Autodesk Fusion 360 part; units mm, degrees
(part 3 of 3)
sketch "Sketch252" plane through (-23.6, 0, 0) normal (1, 0, 0) x (0, 0, -1)
  line L0 (-13.8, -29.146) -> (13.8, -29.146)
  line L1 (13.8, -29.146) -> (13.8, -25.6)
  line L2 (13.8, -25.6) -> (-13.8, -25.6)
  line L3 (-13.8, -25.6) -> (-13.8, -29.146)
loft "Loft72" add profiles "Sketch251", "Sketch252" section 1 section 2 separate body makes body 180
ref_plane "WorkPlane253" through (-24.4, 0, 0) normal (1, 0, 0) x (0, 1, 0)
sketch "Sketch253" plane through (-24.4, 0, 0) normal (1, 0, 0) x (0, 0, -1)
  line L0 (-13.45, -28.8108) -> (13.45, -28.8108)
  line L1 (13.45, -28.8108) -> (13.45, -25.4)
  line L2 (13.45, -25.4) -> (-13.45, -25.4)
  line L3 (-13.45, -25.4) -> (-13.45, -28.8108)
ref_plane "WorkPlane254" through (-21.6, 0, 0) normal (1, 0, 0) x (0, 1, 0)
sketch "Sketch254" plane through (-21.6, 0, 0) normal (1, 0, 0) x (0, 0, -1)
  line L0 (-14.6091, -29.8371) -> (14.6091, -29.8371)
  line L1 (14.6091, -29.8371) -> (14.6091, -26)
  line L2 (14.6091, -26) -> (-14.6091, -26)
  line L3 (-14.6091, -26) -> (-14.6091, -29.8371)
loft "Loft73" add profiles "Sketch253", "Sketch254" section 1 section 2 separate body makes body 181
ref_plane "WorkPlane255" through (-22.4, 0, 0) normal (1, 0, 0) x (0, 1, 0)
sketch "Sketch255" plane through (-22.4, 0, 0) normal (1, 0, 0) x (0, 0, -1)
  line L0 (-14.325, -29.6278) -> (14.325, -29.6278)
  line L1 (14.325, -29.6278) -> (14.325, -25.9)
  line L2 (14.325, -25.9) -> (-14.325, -25.9)
  line L3 (-14.325, -25.9) -> (-14.325, -29.6278)
ref_plane "WorkPlane256" through (-17.6, 0, 0) normal (1, 0, 0) x (0, 1, 0)
sketch "Sketch256" plane through (-17.6, 0, 0) normal (1, 0, 0) x (0, 0, -1)
  line L0 (-15.7, -30.2773) -> (15.7, -30.2773)
  line L1 (15.7, -30.2773) -> (15.7, -26)
  line L2 (15.7, -26) -> (-15.7, -26)
  line L3 (-15.7, -26) -> (-15.7, -30.2773)
loft "Loft74" add profiles "Sketch255", "Sketch256" section 1 section 2 separate body makes body 182
ref_plane "WorkPlane257" through (-18.4, 0, 0) normal (1, 0, 0) x (0, 1, 0)
sketch "Sketch257" plane through (-18.4, 0, 0) normal (1, 0, 0) x (0, 0, -1)
  line L0 (-15.4818, -30.2013) -> (15.4818, -30.2013)
  line L1 (15.4818, -30.2013) -> (15.4818, -26)
  line L2 (15.4818, -26) -> (-15.4818, -26)
  line L3 (-15.4818, -26) -> (-15.4818, -30.2013)
ref_plane "WorkPlane258" through (-11.6, 0, 0) normal (1, 0, 0) x (0, 1, 0)
sketch "Sketch258" plane through (-11.6, 0, 0) normal (1, 0, 0) x (0, 0, -1)
  line L0 (-17.3364, -30.7044) -> (17.3364, -30.7044)
  line L1 (17.3364, -30.7044) -> (17.3364, -26)
  line L2 (17.3364, -26) -> (-17.3364, -26)
  line L3 (-17.3364, -26) -> (-17.3364, -30.7044)
loft "Loft75" add profiles "Sketch257", "Sketch258" section 1 section 2 separate body makes body 183
ref_plane "WorkPlane259" through (-12.4, 0, 0) normal (1, 0, 0) x (0, 1, 0)
sketch "Sketch259" plane through (-12.4, 0, 0) normal (1, 0, 0) x (0, 0, -1)
  line L0 (-17.1182, -30.6602) -> (17.1182, -30.6602)
  line L1 (17.1182, -30.6602) -> (17.1182, -26)
  line L2 (17.1182, -26) -> (-17.1182, -26)
  line L3 (-17.1182, -26) -> (-17.1182, -30.6602)
ref_plane "WorkPlane260" through (-5.6, 0, 0) normal (1, 0, 0) x (0, 1, 0)
sketch "Sketch260" plane through (-5.6, 0, 0) normal (1, 0, 0) x (0, 0, -1)
  line L0 (-18.9727, -30.9332) -> (18.9727, -30.9332)
  line L1 (18.9727, -30.9332) -> (18.9727, -26)
  line L2 (18.9727, -26) -> (-18.9727, -26)
  line L3 (-18.9727, -26) -> (-18.9727, -30.9332)
loft "Loft76" add profiles "Sketch259", "Sketch260" section 1 section 2 separate body makes body 184
ref_plane "WorkPlane261" through (-6.4, 0, 0) normal (1, 0, 0) x (0, 1, 0)
sketch "Sketch261" plane through (-6.4, 0, 0) normal (1, 0, 0) x (0, 0, -1)
  line L0 (-18.7545, -30.9125) -> (18.7545, -30.9125)
  line L1 (18.7545, -30.9125) -> (18.7545, -26)
  line L2 (18.7545, -26) -> (-18.7545, -26)
  line L3 (-18.7545, -26) -> (-18.7545, -30.9125)
ref_plane "WorkPlane262" through (0.4, 0, 0) normal (1, 0, 0) x (0, 1, 0)
sketch "Sketch262" plane through (0.4, 0, 0) normal (1, 0, 0) x (0, 0, -1)
  line L0 (-20.5, -31) -> (20.5, -31)
  line L1 (20.5, -31) -> (20.5, -26)
  line L2 (20.5, -26) -> (-20.5, -26)
  line L3 (-20.5, -26) -> (-20.5, -31)
loft "Loft77" add profiles "Sketch261", "Sketch262" section 1 section 2 separate body makes body 185
ref_plane "WorkPlane263" through (-0.4, 0, 0) normal (1, 0, 0) x (0, 1, 0)
sketch "Sketch263" plane through (-0.4, 0, 0) normal (1, 0, 0) x (0, 0, -1)
  line L0 (-20.3909, -30.9997) -> (20.3909, -30.9997)
  line L1 (20.3909, -30.9997) -> (20.3909, -26)
  line L2 (20.3909, -26) -> (-20.3909, -26)
  line L3 (-20.3909, -26) -> (-20.3909, -30.9997)
ref_plane "WorkPlane264" through (30.4, 0, 0) normal (1, 0, 0) x (0, 1, 0)
sketch "Sketch264" plane through (30.4, 0, 0) normal (1, 0, 0) x (0, 0, -1)
  line L0 (-20.5, -31) -> (20.5, -31)
  line L1 (20.5, -31) -> (20.5, -26)
  line L2 (20.5, -26) -> (-20.5, -26)
  line L3 (-20.5, -26) -> (-20.5, -31)
loft "Loft78" add profiles "Sketch263", "Sketch264" section 1 section 2 separate body makes body 186
ref_plane "WorkPlane265" through (29.6, 0, 0) normal (1, 0, 0) x (0, 1, 0)
sketch "Sketch265" plane through (29.6, 0, 0) normal (1, 0, 0) x (0, 0, -1)
  line L0 (-20.5, -31) -> (20.5, -31)
  line L1 (20.5, -31) -> (20.5, -26)
  line L2 (20.5, -26) -> (-20.5, -26)
  line L3 (-20.5, -26) -> (-20.5, -31)
ref_plane "WorkPlane266" through (60.4, 0, 0) normal (1, 0, 0) x (0, 1, 0)
sketch "Sketch266" plane through (60.4, 0, 0) normal (1, 0, 0) x (0, 0, -1)
  line L0 (-20.5, -31) -> (20.5, -31)
  line L1 (20.5, -31) -> (20.5, -26)
  line L2 (20.5, -26) -> (-20.5, -26)
  line L3 (-20.5, -26) -> (-20.5, -31)
loft "Loft79" add profiles "Sketch265", "Sketch266" section 1 section 2 separate body makes body 187
ref_plane "WorkPlane267" through (59.6, 0, 0) normal (1, 0, 0) x (0, 1, 0)
sketch "Sketch267" plane through (59.6, 0, 0) normal (1, 0, 0) x (0, 0, -1)
  line L0 (-20.5, -31) -> (20.5, -31)
  line L1 (20.5, -31) -> (20.5, -26)
  line L2 (20.5, -26) -> (-20.5, -26)
  line L3 (-20.5, -26) -> (-20.5, -31)
ref_plane "WorkPlane268" through (90.4, 0, 0) normal (1, 0, 0) x (0, 1, 0)
sketch "Sketch268" plane through (90.4, 0, 0) normal (1, 0, 0) x (0, 0, -1)
  line L0 (-20.5, -31) -> (20.5, -31)
  line L1 (20.5, -31) -> (20.5, -26)
  line L2 (20.5, -26) -> (-20.5, -26)
  line L3 (-20.5, -26) -> (-20.5, -31)
loft "Loft80" add profiles "Sketch267", "Sketch268" section 1 section 2 separate body makes body 188
ref_plane "WorkPlane269" through (89.6, 0, 0) normal (1, 0, 0) x (0, 1, 0)
sketch "Sketch269" plane through (89.6, 0, 0) normal (1, 0, 0) x (0, 0, -1)
  line L0 (-20.5, -31) -> (20.5, -31)
  line L1 (20.5, -31) -> (20.5, -26)
  line L2 (20.5, -26) -> (-20.5, -26)
  line L3 (-20.5, -26) -> (-20.5, -31)
ref_plane "WorkPlane270" through (120.4, 0, 0) normal (1, 0, 0) x (0, 1, 0)
sketch "Sketch270" plane through (120.4, 0, 0) normal (1, 0, 0) x (0, 0, -1)
  line L0 (-20.5, -30.9848) -> (20.5, -30.9848)
  line L1 (20.5, -30.9848) -> (20.5, -26)
  line L2 (20.5, -26) -> (-20.5, -26)
  line L3 (-20.5, -26) -> (-20.5, -30.9848)
loft "Loft81" add profiles "Sketch269", "Sketch270" section 1 section 2 separate body makes body 189
ref_plane "WorkPlane271" through (119.6, 0, 0) normal (1, 0, 0) x (0, 1, 0)
sketch "Sketch271" plane through (119.6, 0, 0) normal (1, 0, 0) x (0, 0, -1)
  line L0 (-20.5, -31) -> (20.5, -31)
  line L1 (20.5, -31) -> (20.5, -26)
  line L2 (20.5, -26) -> (-20.5, -26)
  line L3 (-20.5, -26) -> (-20.5, -31)
ref_plane "WorkPlane272" through (122.4, 0, 0) normal (1, 0, 0) x (0, 1, 0)
sketch "Sketch272" plane through (122.4, 0, 0) normal (1, 0, 0) x (0, 0, -1)
  line L0 (-20.4147, -30.8142) -> (20.4147, -30.8142)
  line L1 (20.4147, -30.8142) -> (20.4147, -25.9059)
  line L2 (20.4147, -25.9059) -> (-20.4147, -25.9059)
  line L3 (-20.4147, -25.9059) -> (-20.4147, -30.8142)
loft "Loft82" add profiles "Sketch271", "Sketch272" section 1 section 2 separate body makes body 190
ref_plane "WorkPlane273" through (121.6, 0, 0) normal (1, 0, 0) x (0, 1, 0)
sketch "Sketch273" plane through (121.6, 0, 0) normal (1, 0, 0) x (0, 0, -1)
  line L0 (-20.5, -30.939) -> (20.5, -30.939)
  line L1 (20.5, -30.939) -> (20.5, -26)
  line L2 (20.5, -26) -> (-20.5, -26)
  line L3 (-20.5, -26) -> (-20.5, -30.939)
ref_plane "WorkPlane274" through (132.0667, 0, 0) normal (1, 0, 0) x (0, 1, 0)
sketch "Sketch274" plane through (132.0667, 0, 0) normal (1, 0, 0) x (0, 0, -1)
  line L0 (-18.3534, -28.16) -> (18.3534, -28.16)
  line L1 (18.3534, -28.16) -> (18.3534, -23.6314)
  line L2 (18.3534, -23.6314) -> (-18.3534, -23.6314)
  line L3 (-18.3534, -23.6314) -> (-18.3534, -28.16)
loft "Loft83" add profiles "Sketch273", "Sketch274" section 1 section 2 separate body makes body 191
ref_plane "WorkPlane275" through (131.2667, 0, 0) normal (1, 0, 0) x (0, 1, 0)
sketch "Sketch275" plane through (131.2667, 0, 0) normal (1, 0, 0) x (0, 0, -1)
  line L0 (-18.524, -28.3803) -> (18.524, -28.3803)
  line L1 (18.524, -28.3803) -> (18.524, -23.8196)
  line L2 (18.524, -23.8196) -> (-18.524, -23.8196)
  line L3 (-18.524, -23.8196) -> (-18.524, -28.3803)
ref_plane "WorkPlane276" through (143.7333, 0, 0) normal (1, 0, 0) x (0, 1, 0)
sketch "Sketch276" plane through (143.7333, 0, 0) normal (1, 0, 0) x (0, 0, -1)
  line L0 (-15.8657, -24.9301) -> (15.8657, -24.9301)
  line L1 (15.8657, -24.9301) -> (15.8657, -20.8863)
  line L2 (15.8657, -20.8863) -> (-15.8657, -20.8863)
  line L3 (-15.8657, -20.8863) -> (-15.8657, -24.9301)
loft "Loft84" add profiles "Sketch275", "Sketch276" section 1 section 2 separate body makes body 192
ref_plane "WorkPlane277" through (142.9333, 0, 0) normal (1, 0, 0) x (0, 1, 0)
sketch "Sketch277" plane through (142.9333, 0, 0) normal (1, 0, 0) x (0, 0, -1)
  line L0 (-16.0363, -25.1527) -> (16.0363, -25.1527)
  line L1 (16.0363, -25.1527) -> (16.0363, -21.0745)
  line L2 (16.0363, -21.0745) -> (-16.0363, -21.0745)
  line L3 (-16.0363, -21.0745) -> (-16.0363, -25.1527)
ref_plane "WorkPlane278" through (155.4, 0, 0) normal (1, 0, 0) x (0, 1, 0)
sketch "Sketch278" plane through (155.4, 0, 0) normal (1, 0, 0) x (0, 0, -1)
  line L0 (-13.3779, -21.6616) -> (13.3779, -21.6616)
  line L1 (13.3779, -21.6616) -> (13.3779, -18.1412)
  line L2 (13.3779, -18.1412) -> (-13.3779, -18.1412)
  line L3 (-13.3779, -18.1412) -> (-13.3779, -21.6616)
loft "Loft85" add profiles "Sketch277", "Sketch278" section 1 section 2 separate body makes body 193
ref_plane "WorkPlane279" through (154.6, 0, 0) normal (1, 0, 0) x (0, 1, 0)
sketch "Sketch279" plane through (154.6, 0, 0) normal (1, 0, 0) x (0, 0, -1)
  line L0 (-13.5485, -21.8873) -> (13.5485, -21.8873)
  line L1 (13.5485, -21.8873) -> (13.5485, -18.3294)
  line L2 (13.5485, -18.3294) -> (-13.5485, -18.3294)
  line L3 (-13.5485, -18.3294) -> (-13.5485, -21.8873)
ref_plane "WorkPlane280" through (167.0667, 0, 0) normal (1, 0, 0) x (0, 1, 0)
sketch "Sketch280" plane through (167.0667, 0, 0) normal (1, 0, 0) x (0, 0, -1)
  line L0 (-10.8902, -18.336) -> (10.8902, -18.336)
  line L1 (10.8902, -18.336) -> (10.8902, -15.3961)
  line L2 (10.8902, -15.3961) -> (-10.8902, -15.3961)
  line L3 (-10.8902, -15.3961) -> (-10.8902, -18.336)
loft "Loft86" add profiles "Sketch279", "Sketch280" section 1 section 2 separate body makes body 194
ref_plane "WorkPlane281" through (166.2667, 0, 0) normal (1, 0, 0) x (0, 1, 0)
sketch "Sketch281" plane through (166.2667, 0, 0) normal (1, 0, 0) x (0, 0, -1)
  line L0 (-11.0608, -18.5666) -> (11.0608, -18.5666)
  line L1 (11.0608, -18.5666) -> (11.0608, -15.5843)
  line L2 (11.0608, -15.5843) -> (-11.0608, -15.5843)
  line L3 (-11.0608, -15.5843) -> (-11.0608, -18.5666)
ref_plane "WorkPlane282" through (178.7333, 0, 0) normal (1, 0, 0) x (0, 1, 0)
sketch "Sketch282" plane through (178.7333, 0, 0) normal (1, 0, 0) x (0, 0, -1)
  line L0 (-8.4025, -14.9089) -> (8.4025, -14.9089)
  line L1 (8.4025, -14.9089) -> (8.4025, -12.651)
  line L2 (8.4025, -12.651) -> (-8.4025, -12.651)
  line L3 (-8.4025, -12.651) -> (-8.4025, -14.9089)
loft "Loft87" add profiles "Sketch281", "Sketch282" section 1 section 2 separate body makes body 195
ref_plane "WorkPlane283" through (177.9333, 0, 0) normal (1, 0, 0) x (0, 1, 0)
sketch "Sketch283" plane through (177.9333, 0, 0) normal (1, 0, 0) x (0, 0, -1)
  line L0 (-8.573, -15.1492) -> (8.573, -15.1492)
  line L1 (8.573, -15.1492) -> (8.573, -12.8392)
  line L2 (8.573, -12.8392) -> (-8.573, -12.8392)
  line L3 (-8.573, -12.8392) -> (-8.573, -15.1492)
ref_plane "WorkPlane284" through (190, 0, 0) normal (1, 0, 0) x (0, 1, 0)
sketch "Sketch284" plane through (190, 0, 0) normal (1, 0, 0) x (0, 0, -1)
  line L0 (-6, -11.2) -> (6, -11.2)
  line L1 (6, -11.2) -> (6, -10)
  line L2 (6, -10) -> (-6, -10)
  line L3 (-6, -10) -> (-6, -11.2)
loft "Loft88" add profiles "Sketch283", "Sketch284" section 1 section 2 separate body makes body 196
ref_plane "WorkPlane285" through (-28, 0, 0) normal (1, 0, 0) x (0, 1, 0)
sketch "fair_nose_bulkhead" plane through (-28, 0, 0) normal (1, 0, 0) x (0, 0, -1)
  line L0 (-11.875, -24.5) -> (11.875, -24.5)
  line L1 (11.875, -24.5) -> (11.875, 24.5)
  line L2 (11.875, 24.5) -> (-11.875, 24.5)
  line L3 (-11.875, 24.5) -> (-11.875, -24.5)
  line L4 (-10.5, -23.5) -> (10.5, -23.5)
  line L5 (10.5, -23.5) -> (10.5, 23.5)
  line L6 (10.5, 23.5) -> (-10.5, 23.5)
  line L7 (-10.5, 23.5) -> (-10.5, -23.5)
extrude "Extrude109" add sketch "fair_nose_bulkhead" along normal mid plane 2 separate body makes body 197
ref_plane "WorkPlane286" through (189, 0, 0) normal (1, 0, 0) x (0, 1, 0)
sketch "fair_tail_bulkhead" plane through (189, 0, 0) normal (1, 0, 0) x (0, 0, -1)
  line L0 (-6.2132, -10.2353) -> (6.2132, -10.2353)
  line L1 (6.2132, -10.2353) -> (6.2132, 10.2353)
  line L2 (6.2132, 10.2353) -> (-6.2132, 10.2353)
  line L3 (-6.2132, 10.2353) -> (-6.2132, -10.2353)
extrude "Extrude110" add sketch "fair_tail_bulkhead" along normal mid plane 2 separate body makes body 198
named bodies: "plate_a", "plate_b", "rail_left", "rail_right", "bm_top_s00", "bm_top_s01", "bm_top_s02", "bm_top_s03", "bm_top_s04", "bm_bottom_s00", "bm_bottom_s01", "bm_bottom_s02", "bm_bottom_s03", "bm_bottom_s04", "bm_left_s00", "bm_left_s01", "bm_left_s02", "bm_left_s03", "bm_left_s04", "bm_right_s00", "bm_right_s01", "bm_right_s02", "bm_right_s03", "bm_right_s04", "front_flange", "rear_cap", "graphite_left", "graphite_right", "magnet_N_st0_a0_d0", "magnet_N_st0_a0_d1", "magnet_S_st0_a0_d0", "magnet_S_st0_a0_d1", "magnet_N_st0_a1_d0", "magnet_N_st0_a1_d1", "magnet_S_st0_a1_d0", "magnet_S_st0_a1_d1", "magnet_N_st0_a2_d0", "magnet_N_st0_a2_d1", "magnet_S_st0_a2_d0", "magnet_S_st0_a2_d1", "magnet_N_st0_a3_d0", "magnet_N_st0_a3_d1", "magnet_S_st0_a3_d0", "magnet_S_st0_a3_d1", "magnet_N_st1_a0_d0", "magnet_N_st1_a0_d1", "magnet_S_st1_a0_d0", "magnet_S_st1_a0_d1", "magnet_N_st1_a1_d0", "magnet_N_st1_a1_d1", "magnet_S_st1_a1_d0", "magnet_S_st1_a1_d1", "magnet_N_st1_a2_d0", "magnet_N_st1_a2_d1", "magnet_S_st1_a2_d0", "magnet_S_st1_a2_d1", "magnet_N_st1_a3_d0", "magnet_N_st1_a3_d1", "magnet_S_st1_a3_d0", "magnet_S_st1_a3_d1", "magnet_N_st2_a0_d0", "magnet_N_st2_a0_d1", "magnet_S_st2_a0_d0", "magnet_S_st2_a0_d1", "magnet_N_st2_a1_d0", "magnet_N_st2_a1_d1", "magnet_S_st2_a1_d0", "magnet_S_st2_a1_d1", "magnet_N_st2_a2_d0", "magnet_N_st2_a2_d1", "magnet_S_st2_a2_d0", "magnet_S_st2_a2_d1", "magnet_N_st2_a3_d0", "magnet_N_st2_a3_d1", "magnet_S_st2_a3_d0", "magnet_S_st2_a3_d1", "magnet_N_st3_a0_d0", "magnet_N_st3_a0_d1", "magnet_S_st3_a0_d0", "magnet_S_st3_a0_d1", "magnet_N_st3_a1_d0", "magnet_N_st3_a1_d1", "magnet_S_st3_a1_d0", "magnet_S_st3_a1_d1", "magnet_N_st3_a2_d0", "magnet_N_st3_a2_d1", "magnet_S_st3_a2_d0", "magnet_S_st3_a2_d1", "magnet_N_st3_a3_d0", "magnet_N_st3_a3_d1", "magnet_S_st3_a3_d0", "magnet_S_st3_a3_d1", "magnet_N_st4_a0_d0", "magnet_N_st4_a0_d1", "magnet_S_st4_a0_d0", "magnet_S_st4_a0_d1", "magnet_N_st4_a1_d0", "magnet_N_st4_a1_d1", "magnet_S_st4_a1_d0", "magnet_S_st4_a1_d1", "magnet_N_st4_a2_d0", "magnet_N_st4_a2_d1", "magnet_S_st4_a2_d0", "magnet_S_st4_a2_d1", "magnet_N_st4_a3_d0", "magnet_N_st4_a3_d1", "magnet_S_st4_a3_d0", "magnet_S_st4_a3_d1", "magnet_N_st5_a0_d0", "magnet_N_st5_a0_d1", "magnet_S_st5_a0_d0", "magnet_S_st5_a0_d1", "magnet_N_st5_a1_d0", "magnet_N_st5_a1_d1", "magnet_S_st5_a1_d0", "magnet_S_st5_a1_d1", "magnet_N_st5_a2_d0", "magnet_N_st5_a2_d1", "magnet_S_st5_a2_d0", "magnet_S_st5_a2_d1", "magnet_N_st5_a3_d0", "magnet_N_st5_a3_d1", "magnet_S_st5_a3_d0", "magnet_S_st5_a3_d1", "hood_top", "hood_bottom", "endbar_rear_p", "endbar_rear_n", "f_top_s00", "f_top_s01", "f_top_s02", "f_top_s03", "f_top_s04", "f_top_s05", "f_top_s06", "f_top_s07", "f_top_s08", "f_top_s09", "f_top_s10", "f_top_s11", "f_top_s12", "f_top_s13", "f_top_s14", "f_top_s15", "f_top_s16", "f_bottom_s00", "f_bottom_s01", "f_bottom_s02", "f_bottom_s03", "f_bottom_s04", "f_bottom_s05", "f_bottom_s06", "f_bottom_s07", "f_bottom_s08", "f_bottom_s09", "f_bottom_s10", "f_bottom_s11", "f_bottom_s12", "f_bottom_s13", "f_bottom_s14", "f_bottom_s15", "f_bottom_s16", "f_right_s00", "f_right_s01", "f_right_s02", "f_right_s03", "f_right_s04", "f_right_s05", "f_right_s06", "f_right_s07", "f_right_s08", "f_right_s09", "f_right_s10", "f_right_s11", "f_right_s12", "f_right_s13", "f_right_s14", "f_right_s15", "f_right_s16", "f_left_s00", "f_left_s01", "f_left_s02", "f_left_s03", "f_left_s04", "f_left_s05", "f_left_s06", "f_left_s07", "f_left_s08", "f_left_s09", "f_left_s10", "f_left_s11", "f_left_s12", "f_left_s13", "f_left_s14", "f_left_s15", "f_left_s16", "fair_nose_bulkhead", "fair_tail_bulkhead"
